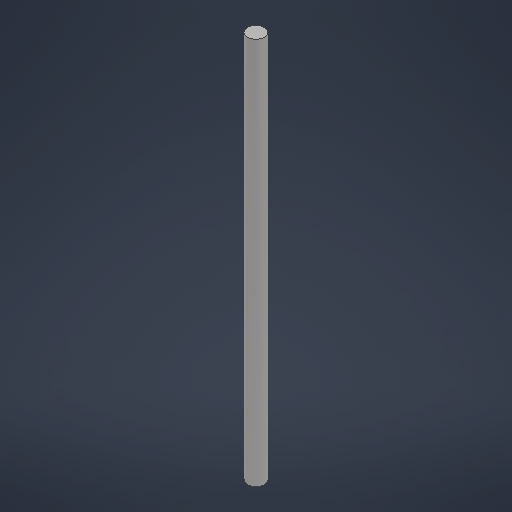
# Autodesk Inventor part: Вал_алюминиевый_8x181
Saved by Autodesk Inventor 2026 (Build 300175050, 175E)
## iProperties
Created: 2026-10-24
Part Number: Вал_алюминиевый_8x181
Material: Алюминий 6061
Document SubType Name: Modeling
Designer: VK7
Density: 2.7 g/cm^3
Appearance: Нержавеющая — шлифованная
Author: VK7
Autodesk Inventor part; units mm, degrees
ref_plane "YZ Plane" through (0, 0, 0) normal (1, 0, 0) x (0, 1, 0)
ref_plane "XZ Plane" through (0, 0, 0) normal (0, 1, 0) x (-1, 0, 0)
ref_plane "XY Plane" through (0, 0, 0) normal (0, 0, 1) x (1, 0, 0)
sketch "Эскиз1" plane through (0, 0, 0) normal (0, 1, 0) x (-1, 0, 0)
  circle A0 centre (0, 0) radius 4
  dimension "d0" = 8
  constraints: 1 centre point, 1 coincident
  measures "d0" diameter of A0
extrude "Выдавливание1" add sketch "Эскиз1" along normal blind 181
